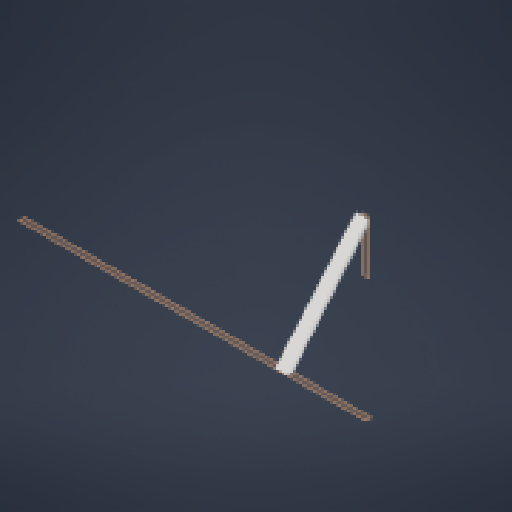
# Autodesk Inventor part: Upper Nose Diagonals
Saved by Autodesk Inventor 2027 (Build 310192000, 192)
## iProperties
Created: 2026-10-18
Part Number: Upper Nose Diagonals
Material: Generic
Document SubType Name: Modeling
Designer: lucas
Density: 1 g/cm^3
Appearance: Default
Author: lucas
Autodesk Inventor part; units mm, degrees
ref_plane "YZ Plane" through (0, 0, 0) normal (1, 0, 0) x (0, 1, 0)
ref_plane "XZ Plane" through (0, 0, 0) normal (0, 1, 0) x (-1, 0, 0)
ref_plane "XY Plane" through (0, 0, 0) normal (0, 0, 1) x (1, 0, 0)
ref_plane "Work Plane1" through (0, 0, 0) normal (0, 0, 1) x (1, 0, 0)
sketch "Sketch1" plane through (0, 0, 0) normal (0, 0, 1) x (1, 0, 0)
  line L0 (0, 0) -> (-88.9, 0)
  line L1 (-88.9, 0) -> (-88.9, -38.1)
  line L2 (-88.9, -38.1) -> (0, -38.1)
  line L3 (0, -38.1) -> (0, 0)
  dimension "d0" = 88.9
  dimension "d1" = 38.1
  constraints: 8 end point, 2 parallel, 1 horizontal, 1 perpendicular
  measures "d0" distance of L1.end L2.end
  measures "d1" distance of L0.end L1.end
ref_plane "Work Plane2" through (774.7, -342.9, 863.6) normal (0, 1, 0) x (-1, 0, 0)
sketch "Sketch2" plane through (774.7, -342.9, 863.6) normal (0, 1, 0) x (-1, 0, 0)
  line L0 (444.5, 38.1) -> (533.4, 38.1)
  line L1 (533.4, 38.1) -> (533.4, 0)
  line L2 (533.4, 0) -> (444.5, 0)
  line L3 (444.5, 0) -> (444.5, 38.1)
  point P0 (774.7, -863.6)
  point P1 (533.4, 38.1)
  dimension "d2" = 38.1
  constraints: 8 end point, 2 parallel, 1 horizontal, 1 perpendicular, 2 other
  measures "d2" distance of L0.end L1.end
loft "Loft1" add profiles "Sketch2", "Sketch1"
body "Solid1"
